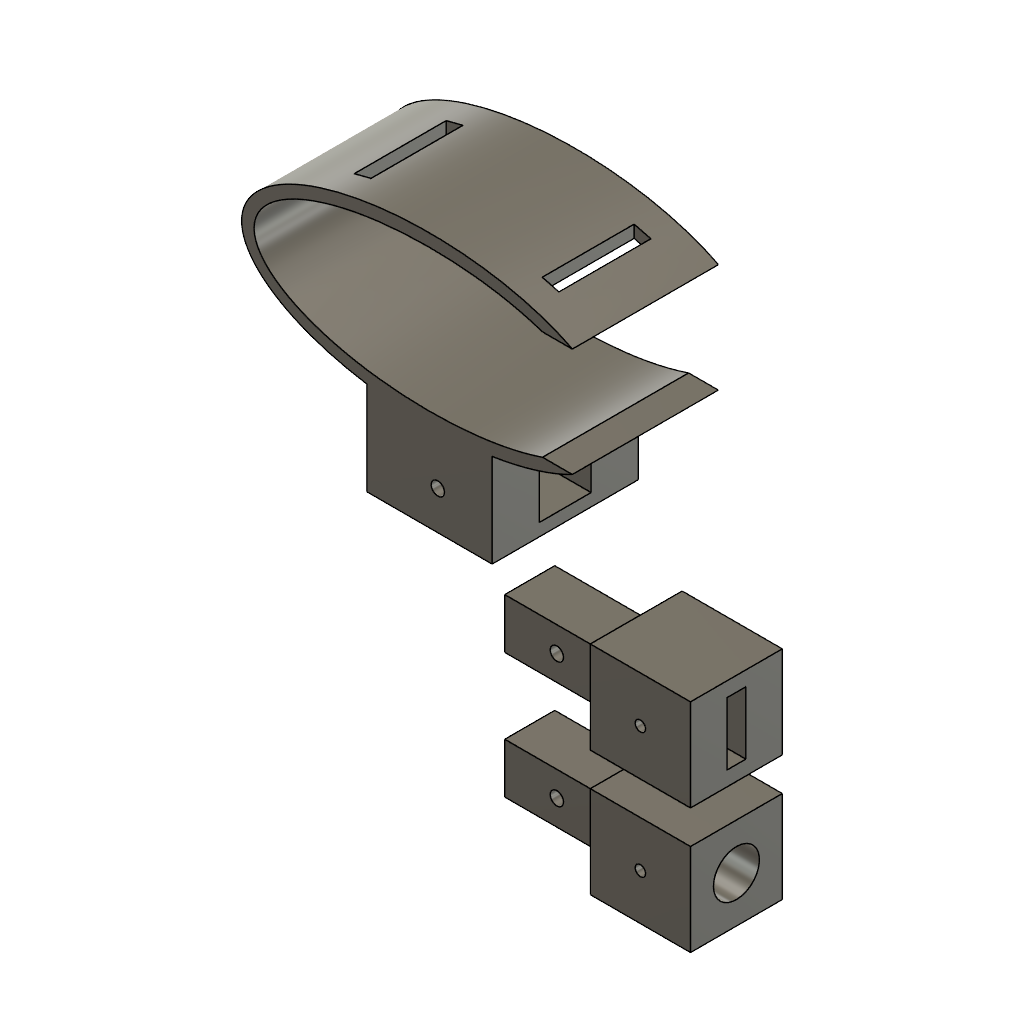
GripCuff_Size_M (Autodesk Fusion 360 design; units mm, degrees)
part number: 2026-10-14-00-49-51-058
part number: 2026-10-14-00-49-51-881
part number: 2026-10-14-00-49-52-563
part number: 2026-10-14-00-49-53-255
Autodesk Fusion 360 part; units mm, degrees
sketch "Boceto1" plane through (0, 0, 0) normal (0, 0, 1) x (1, 0, 0) in component "Cuff_M"
  ellipse E0 centre (0, 0) end of major axis (45, 0) minor radius 20
  line L0 (-45, 0) -> (45, 0) construction
  line L1 (0, 20) -> (0, -20) construction
  constraint coincident E0 L0.start
  constraint coincident E0 L0.end
  constraint coincident E0 L1.start
  constraint coincident E0 L1.end
extrude "Extruir1" add sketch "Boceto1" along normal blind 35 makes body 1 in component "Cuff_M"
ref_plane "PlanoDeObra1" through (0, 0, 0) normal (0, 0, 1) x (1, 0, 0) in component "Cuff_M"
sketch "Boceto2" plane through (0, 0, 0) normal (0, 0, 1) x (1, 0, 0) in component "Cuff_M"
  line L0 (-15, -41.2) -> (15, -41.2)
  line L1 (15, -41.2) -> (15, 0)
  line L2 (15, 0) -> (-15, 0)
  line L3 (-15, 0) -> (-15, -41.2)
extrude "Extruir2" add sketch "Boceto2" along normal blind 35 bodies 1 in component "Cuff_M"
sketch "Boceto3" plane through (0, 0, 0) normal (0, 0, 1) x (1, 0, 0) in component "Cuff_M"
  ellipse E0 centre (0, 0) end of major axis (42, 0) minor radius 17
  line L0 (-42, 0) -> (42, 0) construction
  line L1 (0, 17) -> (0, -17) construction
  constraint coincident E0 L0.start
  constraint coincident E0 L0.end
  constraint coincident E0 L1.start
  constraint coincident E0 L1.end
extrude "Extruir3" cut sketch "Boceto3" along normal blind 35 bodies 1 in component "Cuff_M"
sketch "Boceto4" plane through (0, 0, 0) normal (0, 0, 1) x (1, 0, 0) in component "Cuff_M"
  line L0 (0, -13) -> (50, -13)
  line L1 (50, -13) -> (50, 13)
  line L2 (50, 13) -> (0, 13)
  line L3 (0, 13) -> (0, -13)
extrude "Extruir4" cut sketch "Boceto4" along normal blind 35 bodies 1 in component "Cuff_M"
ref_plane "PlanoDeObra2" through (0, 0, 6.5) normal (0, 0, 1) x (1, 0, 0) in component "Cuff_M"
sketch "Boceto5" plane through (0, 0, 6.5) normal (0, 0, 1) x (1, 0, 0) in component "Cuff_M"
  line L0 (-24.5, 0) -> (-20.5, 0)
  line L1 (-20.5, 0) -> (-20.5, 25)
  line L2 (-20.5, 25) -> (-24.5, 25)
  line L3 (-24.5, 25) -> (-24.5, 0)
  line L4 (20.5, 0) -> (24.5, 0)
  line L5 (24.5, 0) -> (24.5, 25)
  line L6 (24.5, 25) -> (20.5, 25)
  line L7 (20.5, 25) -> (20.5, 0)
extrude "Extruir5" cut sketch "Boceto5" along normal blind 22 bodies 1 in component "Cuff_M"
ref_plane "PlanoDeObra3" through (15, 0, 0) normal (1, 0, 0) x (0, 1, 0) in component "Cuff_M"
sketch "Boceto6" plane through (15, 0, 0) normal (1, 0, 0) x (0, 0, -1) in component "Cuff_M"
  line L0 (-11.3, -38.2) -> (-23.7, -38.2)
  line L1 (-23.7, -38.2) -> (-23.7, -25.8)
  line L2 (-23.7, -25.8) -> (-11.3, -25.8)
  line L3 (-11.3, -25.8) -> (-11.3, -38.2)
extrude "Extruir6" cut sketch "Boceto6" against normal blind 26 bodies 1 in component "Cuff_M"
sketch "Boceto7" plane through (0, 0, 0) normal (0, 0, 1) x (1, 0, 0) in component "Cuff_M"
  circle A0 centre (2, -32) radius 1.6
extrude "Extruir7" cut sketch "Boceto7" along normal through all bodies 1 in component "Cuff_M"
sketch "Boceto1 (2)" plane through (0, 0, 0) normal (1, 0, 0) x (0, 0, -1) in component "Adapter_Flat"
  line L0 (-5, -76) -> (-17, -76)
  line L1 (-17, -76) -> (-17, -64)
  line L2 (-17, -64) -> (-5, -64)
  line L3 (-5, -64) -> (-5, -76)
extrude "Extruir1'" add sketch "Boceto1 (2)" along normal blind 25.5 separate body makes body 2 in component "Adapter_Flat"
ref_plane "PlanoDeObra1" through (25.5, 0, 0) normal (1, 0, 0) x (0, 1, 0) in component "Adapter_Flat"
sketch "Boceto2 (2)" plane through (25.5, 0, 0) normal (1, 0, 0) x (0, 0, -1) in component "Adapter_Flat"
  line L0 (0, -81) -> (-22, -81)
  line L1 (-22, -81) -> (-22, -59)
  line L2 (-22, -59) -> (0, -59)
  line L3 (0, -59) -> (0, -81)
extrude "Extruir2'" add sketch "Boceto2 (2)" along normal blind 24 bodies 2 in component "Adapter_Flat"
ref_plane "PlanoDeObra2" through (49.5, 0, 0) normal (1, 0, 0) x (0, 1, 0) in component "Adapter_Flat"
sketch "Boceto3 (2)" plane through (49.5, 0, 0) normal (1, 0, 0) x (0, 0, -1) in component "Adapter_Flat"
  line L0 (-8.75, -77.5) -> (-13.25, -77.5)
  line L1 (-13.25, -77.5) -> (-13.25, -62.5)
  line L2 (-13.25, -62.5) -> (-8.75, -62.5)
  line L3 (-8.75, -62.5) -> (-8.75, -77.5)
extrude "Extruir3'" cut sketch "Boceto3 (2)" against normal blind 22 bodies 2 in component "Adapter_Flat"
sketch "Boceto4 (2)" plane through (0, 0, 0) normal (0, 0, 1) x (1, 0, 0) in component "Adapter_Flat"
  circle A0 centre (37.5, -70) radius 1.25
extrude "Extruir4'" cut sketch "Boceto4 (2)" along normal through all bodies 2 in component "Adapter_Flat"
sketch "Boceto5 (2)" plane through (0, 0, 0) normal (0, 0, 1) x (1, 0, 0) in component "Adapter_Flat"
  circle A0 centre (12.5, -70) radius 1.6
extrude "Extruir5'" cut sketch "Boceto5 (2)" along normal through all bodies 2 in component "Adapter_Flat"
sketch "Boceto1 (3)" plane through (0, 0, 0) normal (1, 0, 0) x (0, 0, -1) in component "Adapter_Round"
  line L0 (-5, -106) -> (-17, -106)
  line L1 (-17, -106) -> (-17, -94)
  line L2 (-17, -94) -> (-5, -94)
  line L3 (-5, -94) -> (-5, -106)
extrude "Extruir1''" add sketch "Boceto1 (3)" along normal blind 25.5 separate body makes body 3 in component "Adapter_Round"
ref_plane "PlanoDeObra1" through (25.5, 0, 0) normal (1, 0, 0) x (0, 1, 0) in component "Adapter_Round"
sketch "Boceto2 (3)" plane through (25.5, 0, 0) normal (1, 0, 0) x (0, 0, -1) in component "Adapter_Round"
  line L0 (0, -111) -> (-22, -111)
  line L1 (-22, -111) -> (-22, -89)
  line L2 (-22, -89) -> (0, -89)
  line L3 (0, -89) -> (0, -111)
extrude "Extruir2''" add sketch "Boceto2 (3)" along normal blind 24 bodies 3 in component "Adapter_Round"
ref_plane "PlanoDeObra2" through (49.5, 0, 0) normal (1, 0, 0) x (0, 1, 0) in component "Adapter_Round"
sketch "Boceto3 (3)" plane through (49.5, 0, 0) normal (1, 0, 0) x (0, 0, -1) in component "Adapter_Round"
  circle A0 centre (-11, -100) radius 5.5
extrude "Extruir3''" cut sketch "Boceto3 (3)" against normal blind 22 bodies 3 in component "Adapter_Round"
sketch "Boceto4 (3)" plane through (0, 0, 0) normal (0, 0, 1) x (1, 0, 0) in component "Adapter_Round"
  circle A0 centre (37.5, -100) radius 1.25
extrude "Extruir4''" cut sketch "Boceto4 (3)" along normal through all bodies 3 in component "Adapter_Round"
sketch "Boceto5 (3)" plane through (0, 0, 0) normal (0, 0, 1) x (1, 0, 0) in component "Adapter_Round"
  circle A0 centre (12.5, -100) radius 1.6
extrude "Extruir5''" cut sketch "Boceto5 (3)" along normal through all bodies 3 in component "Adapter_Round"
component "Cuff_M" placed x (1, 0, 0) y (0, 1, 0) z (0, 0, 1) at (0, 0, 0)
component "Adapter_Flat" placed x (1, 0, 0) y (0, 1, 0) z (0, 0, 1) at (0, 0, 0)
component "Adapter_Round" placed x (1, 0, 0) y (0, 1, 0) z (0, 0, 1) at (0, 0, 0)
equation "d17 = -( 26.00 mm )"
equation "d28 = -( 22.00 mm )"
equation "d40 = -( 22.00 mm )"
named bodies: "Cuff_M", "Adapter_Flat", "Adapter_Round"
